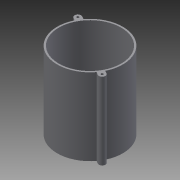
# Autodesk Inventor part: bezzel
Saved by Autodesk Inventor 2014 (Build 180170000, 170)
## iProperties
Created: 2014-09-17
Part Number: bezzel
Material: Všeobecné
Document SubType Name: Modeling
Designer: brodhaq
Density: 1 g/cm^3
Appearance: Výchozí
Author: brodhaq
Autodesk Inventor part; units mm, degrees
ref_plane "YZ Plane" through (0, 0, 0) normal (1, 0, 0) x (0, 1, 0)
ref_plane "XZ Plane" through (0, 0, 0) normal (0, 1, 0) x (-1, 0, 0)
ref_plane "XY Plane" through (0, 0, 0) normal (0, 0, 1) x (1, 0, 0)
sketch "Náčrt1" plane through (0, 0, 0) normal (0, 0, 1) x (1, 0, 0)
  circle A0 centre (-35.5781, -31.5045) radius 38.5
  circle A1 centre (2.4219, -54.5045) radius 1.5
  circle A2 centre (-73.5781, -8.5045) radius 1.5
  circle A3 centre (-35.5781, -31.5045) radius 38.5
  line L0 (-73.5781, -8.5045) -> (2.4219, -54.5045) construction
  line L1 (-71.5069, -5.0825) -> (-67.9853, -7.214)
  line L2 (-75.6493, -11.9265) -> (-72.1277, -14.058)
  arc A4 (-71.5069, -5.0825) -> (-75.6493, -11.9265) centre (-73.5781, -8.5045) ccw
  line L3 (0.3507, -57.9265) -> (-3.1552, -55.7739)
  line L4 (4.5364, -51.1091) -> (0.9216, -49.0549)
  arc A5 (0.3073, -57.8999) -> (4.2566, -50.9501) centre (2.4219, -54.5045) ccw
  arc A6 (-72.1277, -14.058) -> (-3.1552, -55.7739) centre (-35.5781, -31.5045) ccw
  arc A7 (0.9216, -49.0549) -> (-67.9853, -7.214) centre (-35.5781, -31.5045) ccw
  arc A8 (0.9216, -49.0549) -> (-67.9853, -7.214) centre (-35.5781, -31.5045) ccw
  arc A9 (-72.1277, -14.058) -> (-3.1552, -55.7739) centre (-35.5781, -31.5045) ccw
  dimension "d5" = 77
  dimension "d29" = 3
  dimension "d30" = 3
  constraints: 14 point on circle, 10 centre point, 10 end point, 4 coincident, 2 parallel, 2 point on line, 2 tangent, 1 concentric
  measures "d5" diameter of A0
  measures "d29" diameter of A1
  measures "d30" diameter of A2
extrude "Vysunutí9" add sketch "Náčrt1" along normal blind 95 contours L1 A7 L4 A5 L3 A6 L2 A4
